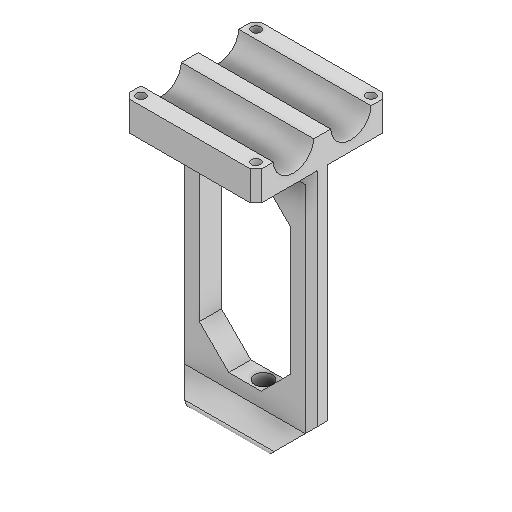
# Autodesk Inventor part: 3DP_PLA_Antenna_Boom_2_4GHz_2x2_Phased_Array_REVB
Saved by Autodesk Inventor 2027 (Build 310192060, 192F)
## iProperties
Created: 2026-01-18
Part Number: 3DP_PLA_Antenna_Boom_2_4GHz_2x2_Phased_Array_REVB
Material: Generic
Document SubType Name: Modeling
Designer: Andrzej
Density: 1 g/cm^3
Appearance: Default
Author: Andrzej
Autodesk Inventor part; units mm, degrees
ref_plane "YZ Plane" through (0, 0, 0) normal (1, 0, 0) x (0, 1, 0)
ref_plane "XZ Plane" through (0, 0, 0) normal (0, 1, 0) x (-1, 0, 0)
ref_plane "XY Plane" through (0, 0, 0) normal (0, 0, 1) x (1, 0, 0)
sketch "Sketch1" plane through (0, 0, 0) normal (0, 1, 0) x (-1, 0, 0)
  line L0 (45, 45) -> (-45, 45)
  line L1 (-45, 45) -> (-45, -45)
  line L2 (-45, -45) -> (45, -45)
  line L3 (45, -45) -> (45, 45)
  point P0 (0, 0)
  dimension "d0" = 90
  dimension "d1" = 90
  dimension "d2" = 45
  dimension "d3" = 45
  constraints: 8 end point, 2 parallel, 1 horizontal, 1 perpendicular
  measures "d0" distance of L0.start L0.end
  measures "d1" distance of L2.end L0.start
  measures "d2" distance from line of point (0, 0) L0
  measures "d3" distance from line of L3 point (0, 0)
extrude "Extrusion1" add sketch "Sketch1" along normal blind 20
sketch "Sketch2" plane through (45, 0, 45) normal (1, 0, 0) x (0, 0, -1)
  circle A0 centre (25.5, 20.5) radius 13.75
  circle A1 centre (64.5, 20.5) radius 13.75
  line L0 (0, 0) -> (90, 0) projected
  line L1 (90, 0) -> (90, 20) projected
  line L2 (0, 20) -> (90, 20) projected
  line L3 (0, 0) -> (0, 20) projected
  point P0 (45, 0)
  dimension "d6" = 27.5
  dimension "d7" = 27.5
  dimension "d8" = 0.5
  dimension "d9" = 39
  dimension "d10" = 90
  dimension "d11" = 25.5
  constraints: 2 centre point, 1 horizontal alignment
  measures "d6" diameter of A0
  measures "d7" diameter of A1
  measures "d8" distance from line of L2 A0.centre
  measures "d9" distance of A1.centre A0.centre
  measures "d10" distance between parallel lines of L1 L3
  measures "d11" distance from line of L3 A0.centre
extrude "Extrusion2" cut sketch "Sketch2" against normal through all contours A0 L2 | L2 A0 | L2 A1 | A1 L2
sketch "Sketch3" plane through (0, 0, 0) normal (0, -1, 0) x (1, 0, 0)
  line L0 (45, 45) -> (45, -45) projected
  line L1 (-45, 45) -> (45, 45) projected
  line L2 (-45, -45) -> (-45, 45) projected
  line L3 (45, -45) -> (-45, -45) projected
  line L4 (-45, -7.5) -> (45, -7.5)
  line L5 (-45, 7.5) -> (45, 7.5)
  line L6 (-7.5, -7.5) -> (-7.5, -45)
  line L7 (7.5, -7.5) -> (7.5, -45)
  line L8 (-7.5, 7.5) -> (-7.5, 45)
  line L9 (7.5, 7.5) -> (7.5, 45)
  line L10 (7.5, -7.5) -> (7.5, 7.5)
  line L11 (-7.5, -7.5) -> (-7.5, 7.5)
  point P0 (0, 0)
  dimension "d14" = 15
  dimension "d15" = 7.5
  dimension "d16" = 15
  dimension "d17" = 15
  dimension "d18" = 7.5
  dimension "d19" = 7.5
  constraints: 16 end point, 12 point on line, 6 perpendicular
  measures "d14" distance between parallel lines of L5 L4
  measures "d15" distance from line of point (0, 0) L4
  measures "d16" distance between parallel lines of L7 L6
  measures "d17" distance between parallel lines of L9 L8
  measures "d18" distance from line of point (0, 0) L6
  measures "d19" distance from line of point (0, 0) L8
extrude "Extrusion3" add sketch "Sketch3" along normal blind 168.75 contours L0 L4 L10 L5 | L10 L4 L11 L5 | L11 L4 L2 L5
sketch "Sketch4" plane through (0, 20, 0) normal (0, 1, 0) x (1, 0, 0)
  line L0 (-45, 33.2409) -> (45, 33.2409) projected
  line L1 (45, 33.2409) -> (45, 45) projected
  line L2 (45, 45) -> (-45, 45) projected
  line L3 (-45, 45) -> (-45, 33.2409) projected
  line L4 (45, -33.2409) -> (-45, -33.2409) projected
  line L5 (-45, -33.2409) -> (-45, -45) projected
  line L6 (-45, -45) -> (45, -45) projected
  line L7 (45, -45) -> (45, -33.2409) projected
  point P0 (0, 0)
  point P1 (39, 39.1205)
  point P2 (-39, 39.1205)
  point P3 (-39, -39.1205)
  point P4 (39, -39.1205)
  dimension "d22" = 6
  dimension "d23" = 6
  dimension "d24" = 11.7591
  dimension "d25" = 11.7591
  dimension "d26" = 5.8796
  dimension "d27" = 5.8796
  constraints: 2 horizontal alignment, 2 vertical alignment
  measures "d22" distance from line of point (39, 39.12) L1
  measures "d23" distance from line of L3 point (-39, 39.12)
  measures "d24" distance between parallel lines of L2 L0
  measures "d25" distance between parallel lines of L6 L4
  measures "d26" distance from line of L2 point (39, 39.12)
  measures "d27" distance from line of L6 point (39, -39.12)
hole "Hole1" at (39, 20, -39.1205) at (-39, 20, -39.1205) at (-39, 20, 39.1205) at (39, 20, 39.1205) direction (0, -1, 0) diameter 6.2 end through all
chamfer "Chamfer1" distance 4 angle 45 8 edges at (-45, 10, -45) (-45, 10, 45) (45, -84.375, -7.5) (45, -84.375, 7.5) (-45, -84.375, 7.5) (-45, -84.375, -7.5) (45, 10, 45) (45, 10, -45)
sketch "Sketch5" plane through (0, -168.75, 0) normal (0, -1, 0) x (1, 0, 0)
  line L0 (-45, -30) -> (45, -30)
  line L1 (45, -30) -> (45, 30)
  line L2 (45, 30) -> (-45, 30)
  line L3 (-45, 30) -> (-45, -30)
  point P0 (0, 0)
  dimension "d41" = 90
  dimension "d42" = 60
  dimension "d43" = 30
  dimension "d44" = 45
  constraints: 8 end point, 2 parallel, 1 horizontal, 1 perpendicular
  measures "d41" distance of L0.start L0.end
  measures "d42" distance of L0.end L1.end
  measures "d43" distance from line of point (0, 0) L0
  measures "d44" distance from line of point (0, 0) L3
extrude "Extrusion4" add sketch "Sketch5" against normal blind 6
chamfer "Chamfer3" distance 25 angle 45 4 edges at (45, -165.75, -30) (-45, -165.75, -30) (-45, -165.75, 30) (45, -165.75, 30)
chamfer "Chamfer4" distance 8 angle 45 4 edges at (0, 0, 7.5) (0, 0, -7.5) (0, -162.75, -7.5) (0, -162.75, 7.5)
sketch "Sketch7" plane through (0, -168.75, 0) normal (0, -1, 0) x (1, 0, 0)
  circle A0 centre (5, 0) radius 6
  point P0 (0, 0)
  dimension "d99" = 12
  dimension "d100" = 5
  constraints: 1 centre point
  measures "d99" diameter of A0
  measures "d100" distance of A0.centre point (0, 0)
extrude "Extrusion6" cut sketch "Sketch7" against normal blind 50
chamfer "Chamfer6" distance 1 angle 45 1 edges at (-1, -168.75, 0)
sketch "Sketch8" plane through (-41, -154.75, 7.5) normal (0, 0, 1) x (1, 0, 0)
  line L0 (82, 0) -> (0, 0) projected
  line L1 (82, 146.75) -> (82, 0) projected
  line L2 (0, 146.75) -> (82, 146.75) projected
  line L3 (0, 0) -> (0, 146.75) projected
  line L4 (72, 10) -> (10, 10)
  line L5 (10, 10) -> (10, 136.75)
  line L6 (10, 136.75) -> (72, 136.75)
  line L7 (72, 136.75) -> (72, 10)
  point P0 (41, 154.75)
  dimension "d79" = 10
  constraints: 8 end point, 3 other
  measures "d79" distance between parallel lines of L1 L7
extrude "Extrusion7" cut sketch "Sketch8" against normal blind 50 contours L4 L5 L6 L7
chamfer "Chamfer7" distance 20 angle 45 4 edges at (-31, -18, 0) (31, -18, 0) (31, -144.75, 0) (-31, -144.75, 0)
chamfer "Chamfer9" distance 18 angle 45 1 edges at (-45, -168.75, 0)
chamfer "Chamfer10" distance 18 angle 45 1 edges at (45, -168.75, 0)
sketch "Sketch9" plane through (0, -168.75, 0) normal (0, -1, 0) x (1, 0, 0)
  line L0 (27, 23) -> (27, -23) projected
  line L1 (20, 30) -> (27, 23) projected
  line L2 (20, 30) -> (-20, 30) projected
  line L3 (-27, 23) -> (-20, 30) projected
  line L4 (-27, -23) -> (-27, 23) projected
  line L5 (-20, -30) -> (-27, -23) projected
  line L6 (-20, -30) -> (20, -30) projected
  line L7 (27, -23) -> (20, -30) projected
  line L8 (-27, 23) -> (27, 23)
  line L9 (27, -23) -> (-27, -23)
  point P0 (0, 0)
  constraints: 4 end point, 2 horizontal
extrude "Extrusion8" cut sketch "Sketch9" against normal blind 50 contours L8 L3 L2 L1 | L7 L6 L5 L9
sketch "Sketch10" plane through (-45, 20.5, 19.5) normal (-1, 0, 0) x (0, 0, 1)
  line L0 (-35, -183.25) -> (-27, -175.25) projected
  line L1 (-12, -175.25) -> (-4, -183.25) projected
  line L2 (-4, -183.25) -> (6.0157, -193.2657)
  line L3 (6.0157, -193.2657) -> (6.0157, -175.25)
  line L4 (6.0157, -175.25) -> (-12, -175.25)
  line L5 (-35, -183.25) -> (-46.3794, -194.6294)
  line L6 (-46.3794, -194.6294) -> (-46.3794, -175.25)
  line L7 (-46.3794, -175.25) -> (-27, -175.25)
  point P0 (-19.5, -20.5)
  constraints: 12 end point, 4 perpendicular, 1 point on line, 1 vertical
extrude "Extrusion9" cut sketch "Sketch10" against normal through all
fillet "Fillet1" radius 2 2 edges at (0, -168.75, -21.5) (0, -168.75, 21.5)
equation "\"d1\" = d0"
equation "\"d2\" = 0.5 * d1"
equation "\"d3\" = 0.5 * d0"
equation "\"d11\" = -0.5 * d9 + 0.5 * d10"
equation "\"d15\" = 0.5 * d14"
equation "\"d16\" = d14"
equation "\"d17\" = d16"
equation "\"d18\" = 0.5 * d14"
equation "\"d19\" = d18"
equation "\"d23\" = d22"
equation "\"d26\" = 0.5 * d24"
equation "\"d27\" = 0.5 * d25"
equation "\"d43\" = 0.5 * d42"
equation "\"d44\" = 0.5 * d41"
body "Solid1"
